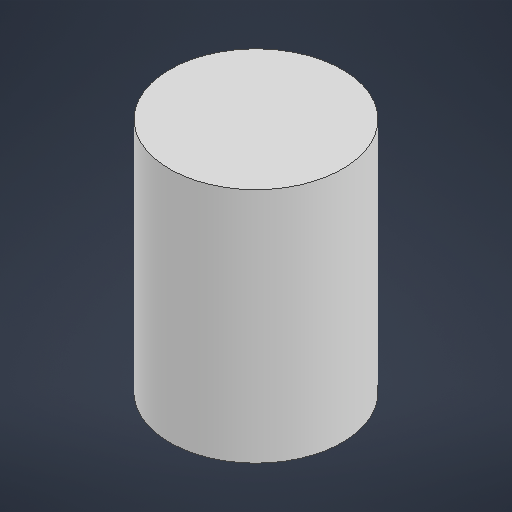
# Autodesk Inventor part: PuntaTCP
Saved by Autodesk Inventor 2027.1 (Build 311270010, 270A)
## iProperties
Created: 2026-09-15
Part Number: PuntaTCP
Material: Genérico
Document SubType Name: Modeling
Designer: felip
Density: 1 g/cm^3
Appearance: Valor por defecto
Author: felip
Autodesk Inventor part; units mm, degrees
ref_plane "YZ Plane" through (0, 0, 0) normal (1, 0, 0) x (0, 1, 0)
ref_plane "XZ Plane" through (0, 0, 0) normal (0, 1, 0) x (-1, 0, 0)
ref_plane "XY Plane" through (0, 0, 0) normal (0, 0, 1) x (1, 0, 0)
sketch "Boceto1" plane through (0, 0, 0) normal (0, 0, 1) x (1, 0, 0)
  line L0 (0, 0) -> (0, 3.5)
  line L1 (0, 3.5) -> (-2.55, 3.5)
  line L2 (-2.55, 3.5) -> (-2.55, -3.5)
  line L3 (-2.55, -3.5) -> (0, -3.5)
  line L4 (0, -3.5) -> (0, 0)
  line L5 (0, 0) -> (0, 7.9742) construction
  dimension "d0" = 3.5
  dimension "d1" = 2.55
  dimension "d2" = 7
  constraints: 12 end point, 2 perpendicular, 2 vertical, 1 collinear, 1 horizontal
  measures "d0" distance of L0.start L0.end
  measures "d1" distance of L0.end L1.end
  measures "d2" distance of L1.end L2.end
revolve "Revolución1" add sketch "Boceto1" angle 360 about axis through (0, 0, 0) along (0, 1, 0)
